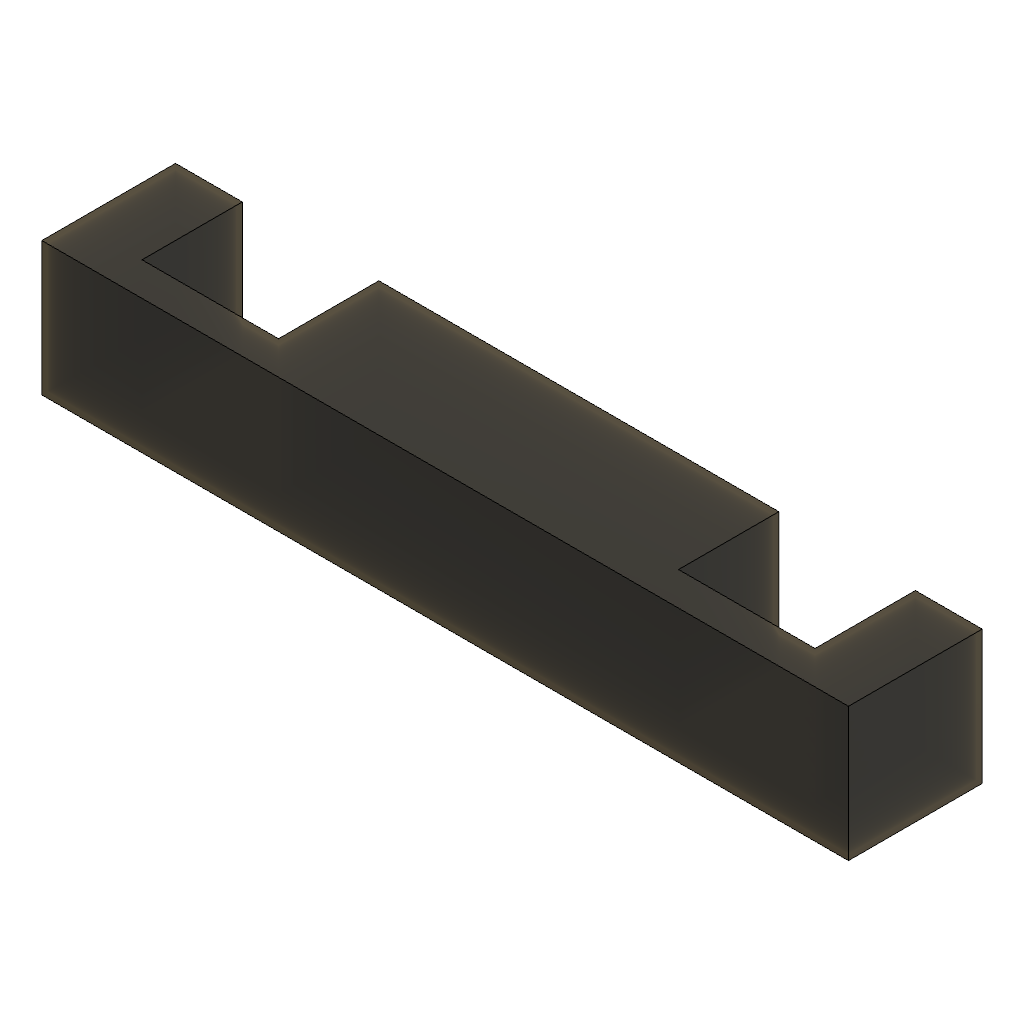
entrelape_bases_carro (Autodesk Fusion 360 design; units mm, degrees)
Autodesk Fusion 360 part; units mm, degrees
sketch "Boceto1" plane through (0, 0, 0) normal (0, 1, 0) x (1, 0, 0)
  line L0 (-30.15, 0) -> (0, 0)
  line L1 (0, 0) -> (0, 10)
  line L2 (0, 10) -> (-14.95, 10)
  line L3 (-30.15, 10) -> (-30.15, 0)
  line L4 (-14.95, 10) -> (-14.95, 2.5)
  line L5 (-14.95, 2.5) -> (-25.15, 2.5)
  line L6 (-25.15, 2.5) -> (-25.15, 10)
  line L7 (-25.15, 10) -> (-30.15, 10)
  line L8 (30.15, 10) -> (30.15, 0)
  line L9 (25.15, 10) -> (30.15, 10)
  line L10 (25.15, 2.5) -> (25.15, 10)
  line L11 (14.95, 2.5) -> (25.15, 2.5)
  line L12 (30.15, 0) -> (0, 0)
  line L13 (14.95, 10) -> (14.95, 2.5)
  line L14 (0, 10) -> (14.95, 10)
  dimension "d1" = 14.95
  dimension "d3" = 7.5
  dimension "d4" = 10
  dimension "d5" = 10.2
  dimension "d6" = 7.5
  dimension "d7" = 5
  dimension "d8" = 30.15
  dimension "d9" = 10
  constraint coincident L0.end L1.start
  constraint horizontal L0
  constraint perpendicular L0 L1
  constraint perpendicular L1 L2
  constraint perpendicular L2 L4
  constraint perpendicular L3 L5
  constraint perpendicular L5 L6
  constraint perpendicular L3 L7
  constraint symmetric L0.start L1 L8.end
  constraint symmetric L0.end L1 L12.end
  constraint symmetric L2.start L1 L14.start
  constraint symmetric L1 L2.end L13.start
  constraint symmetric L1 L4.end L11.start
  constraint symmetric L1 L5.end L10.start
  constraint symmetric L1 L6.end L9.start
  constraint symmetric L1 L3.start L8.start
  measures "d1" distance of L1.end L2.end
  measures "d3" distance of L2.end L4.end
  measures "d4" distance of L0.end L1.end
  measures "d5" distance of L4.end L5.end
  measures "d6" distance of L5.end L6.end
  measures "d7" distance of L6.end L3.start
  measures "d8" distance of L0.start L0.end
  measures "d9" distance of L0.start L3.start
extrude "Extruir1" add sketch "Boceto1" along normal blind 10
equation "d1 = ( 29.9 / 2 ) * 1 mm"
